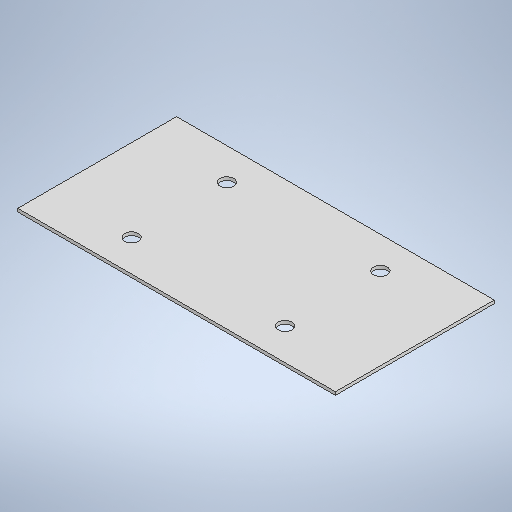
# Autodesk Inventor part: DMF-7xxx 4hole plate
Saved by Autodesk Inventor 2026.2 (Build 302298000, 298)
## iProperties
Created: 2026-06-04
Part Number: DMF-7xxx 4hole plate
Material: Generic
Description: DIE16(5)|\ 90°|corrY -___°|X_____|bom___
Document SubType Name: Sheet Metal
Designer: admin
Stock Number: DMF-4103
Mass: 1762.25 g
Surface Area: 2283.33 cm^2
Volume: 220.281 cm^3
Density: 1 g/cm^3
Flat Pattern Width: 15 cm
Flat Pattern Length: 30 cm
Flat Pattern Area: 450 cm^2
Sheet Metal Rule: Default
Sheet Metal Width: 150,000 mm
Sheet Metal Length: 300,000 mm
Sheet Metal Area: 45000,000 mm^2
Appearance: Default
Author: admin
Autodesk Inventor part; units mm, degrees
ref_plane "YZ Plane" through (0, 0, 0) normal (1, 0, 0) x (0, 1, 0)
ref_plane "XZ Plane" through (0, 0, 0) normal (0, 1, 0) x (-1, 0, 0)
ref_plane "XY Plane" through (0, 0, 0) normal (0, 0, 1) x (1, 0, 0)
sketch "Sketch10" plane through (0, 0, 0) normal (0, 0, 1) x (1, 0, 0)
  line L0 (-150, 75) -> (150, 75)
  line L1 (150, 75) -> (150, -75)
  line L2 (150, -75) -> (-150, -75)
  line L3 (-150, -75) -> (-150, 75)
  line L4 (-150, 75) -> (150, -75) construction
  line L5 (150, 75) -> (-150, -75) construction
  point P0 (0, 0)
  dimension "d200" = 300
  dimension "d201" = 150
  measures "d200" distance of L1.end L2.end
  measures "d201" distance of L0.end L1.end
extrude "Plate8" add sketch "Sketch10" along normal blind 3
sketch "Sketch11" plane through (0, 0, 3) normal (0, 0, 1) x (1, 0, 0)
  line L0 (-72.5, -45) -> (72.5, -45) construction
  line L1 (72.5, -45) -> (72.5, 45) construction
  line L2 (72.5, 45) -> (-72.5, 45) construction
  line L3 (-72.5, 45) -> (-72.5, -45) construction
  line L4 (-72.5, -45) -> (72.5, 45) construction
  line L5 (72.5, -45) -> (-72.5, 45) construction
  circle A0 centre (-72.5, 45) radius 6.5
  circle A1 centre (72.5, 45) radius 6.5
  circle A2 centre (72.5, -45) radius 6.5
  circle A3 centre (-72.5, -45) radius 6.5
  point P0 (0, 0)
  dimension "d203" = 13
  dimension "d204" = 145
  dimension "d205" = 90
  constraints: 12 end point, 4 centre point, 4 coincident, 3 equal radius, 2 midpoint, 2 parallel, 1 horizontal, 1 perpendicular
  measures "d203" diameter of A0
  measures "d204" distance of L1.end L2.end
  measures "d205" distance of L2.end L0.start
extrude "Cut2" cut sketch "Sketch11" against normal blind 3
body "Solid4"
